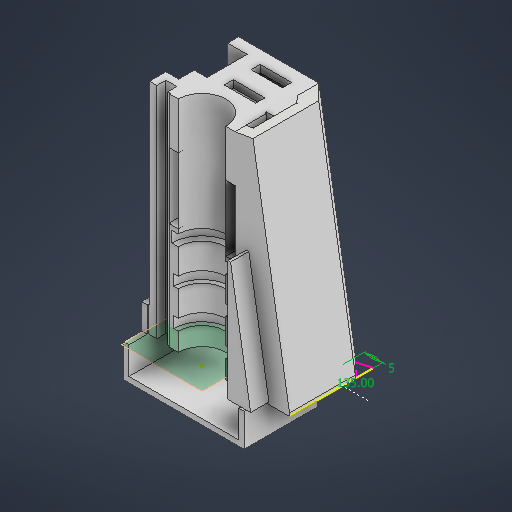
# Autodesk Inventor part: bottom2
Saved by Autodesk Inventor 2026.3 (Build 303398000, 398)
## iProperties
Created: 2026-07-23
Part Number: bottom2
Material: Generic
Document SubType Name: Modeling
Designer: BenFr
Density: 1 g/cm^3
Appearance: Default
Author: BenFr
Autodesk Inventor part; units mm, degrees
ref_plane "YZ Plane" through (0, 0, 0) normal (1, 0, 0) x (0, 1, 0)
ref_plane "XZ Plane" through (0, 0, 0) normal (0, 1, 0) x (-1, 0, 0)
ref_plane "XY Plane" through (0, 0, 0) normal (0, 0, 1) x (1, 0, 0)
sketch "Sketch1" plane through (0, 0, 0) normal (0, 1, 0) x (-1, 0, 0)
  line L0 (-10, 0) -> (0, 0)
  circle A0 centre (0, 0) radius 9
  circle A1 centre (0, 0) radius 6.5
  line L1 (0, 0) -> (9, 0)
  point P0 (6.5, 0)
  point P1 (-9, 0)
  point P2 (-6.5, 0)
  dimension "d1" = 18
  dimension "d0" = 10
  dimension "d2" = 13
  constraints: 4 end point, 2 coincident, 2 horizontal, 1 centre point, 3 other
  measures "d0" distance of L0.start L0.end
  measures "d2" diameter of A1
extrude "Extrusion1" add sketch "Sketch1" along normal blind 60 contours A0 L1 A1 L0 picked at (-3.9988, 7.0571)
sketch "Sketch2" plane through (9, 0, 0) normal (0, 0, -1) x (-1, 0, 0)
  line L0 (0, 60) -> (-10, 0)
  line L1 (-10, 0) -> (0, 0)
  line L2 (0, 0) -> (0, 60)
  line L3 (0, 0) -> (0, 60) projected
  point P0 (9, 0)
  dimension "d5" = 10
  constraints: 6 end point, 2 collinear, 1 horizontal, 1 perpendicular
  measures "d5" distance of L0.end L1.end
extrude "Extrusion2" add sketch "Sketch2" against normal blind 9
sketch "Sketch3" plane through (9, 60, 9) normal (0.9863939, 0.164399, 0) x (0, 0, -1)
  line L0 (9, -60.8276) -> (6, -60.8276)
  line L1 (6, -60.8276) -> (6, 0)
  line L2 (6, 0) -> (9, 0)
  line L3 (9, 0) -> (9, -60.8276)
  line L4 (9, 0) -> (0, 0) projected
  line L5 (9, -60.8276) -> (0, -60.8276) projected
  point P0 (9, -57.704)
  point P1 (7.5, 0)
  point P2 (4.5, -60.8276)
  dimension "d8" = 3
  constraints: 8 end point, 3 point on line, 2 midpoint, 2 parallel, 1 horizontal, 1 perpendicular
  measures "d8" distance of L1.end L2.end
extrude "Extrusion3" add sketch "Sketch3" along normal blind 5
sketch "Sketch4" plane through (19, 0, 3) normal (0, 0, 1) x (0.9863939, 0.164399, 0)
  line L0 (0, 60.8276) -> (5, 60.8276) projected
  line L1 (5, 60.8276) -> (2, 60.8276)
  line L2 (2, 60.8276) -> (2, 0)
  line L3 (2, 0) -> (5, 0)
  line L4 (5, 0) -> (5, 60.8276)
  line L5 (0, 0) -> (5, 0) projected
  point P0 (-18.7415, 3.1236)
  point P1 (2, 60.8276)
  dimension "d11" = 3
  constraints: 8 end point, 2 parallel, 1 collinear, 1 horizontal, 1 perpendicular
  measures "d11" distance of L3.end L2.end
extrude "Extrusion4" add sketch "Sketch4" along normal blind 6
sketch "Sketch5" plane through (9, 0, 9) normal (0, 0, 1) x (1, 0, 0)
  line L0 (0, 60) -> (-18, 60) projected
  line L1 (0, 0) -> (-9, 0)
  line L2 (-9, 0) -> (-9, 60)
  line L3 (-9, 60) -> (0, 60)
  line L4 (0, 60) -> (0, 0)
  line L5 (0, 60) -> (0, 0) projected
  point P0 (-9, 0)
  constraints: 8 end point, 2 parallel, 1 collinear, 1 horizontal, 1 midpoint, 1 perpendicular
extrude "Extrusion5" add sketch "Sketch5" against normal up to surface round surface about axis through (0, 0, 0) along (0, 1, 0) radius 9 far side no
ref_plane "Work Plane2" through (0, 5, 0) normal (0, -1, 0) x (1, 0, 0)
sketch "Sketch6" plane through (0, 5, 0) normal (0, -1, 0) x (1, 0, 0)
  circle A0 centre (0, 0) radius 7.75
  dimension "d17" = 15.5
  constraints: 1 centre point, 1 coincident
  measures "d17" diameter of A0
extrude "Extrusion6" cut sketch "Sketch6" against normal blind 3
sketch "Sketch7" plane through (19, 0, 0) normal (0, 0, -1) x (-1, 0, 0)
  line L0 (10, 60) -> (19, 60) projected
  line L1 (0, 0) -> (10, 60) projected
  line L2 (10, 60) -> (0, 0)
  line L3 (19, 0) -> (0, 0) projected
  line L4 (0.7083, 0.6) -> (6.9, 0.6)
  line L5 (6.9, 0.6) -> (6.9, 37.7503)
  line L6 (6.9, 37.7503) -> (0.7083, 0.6)
  line L7 (0, 0) -> (12.5, 0) projected
  line L8 (19, -12.1644) -> (19, 72.9864) projected
  line L9 (10, 60) -> (10, 0)
  line L10 (0, 0) -> (-4.932, 0.822) projected
  line L11 (0, 0) -> (10, 0)
  line L12 (6.1937, 33.5125) -> (6.1937, 33.5125)
  line L13 (6.1937, 33.5125) -> (6.9, 33.5125)
  point P0 (5, 0)
  dimension "d27" = 3.1
  dimension "d28" = 0.6
  dimension "d29" = 0.6
  constraints: 16 end point, 4 perpendicular, 4 point on line, 2 collinear, 2 parallel, 1 horizontal, 1 midpoint
  measures "d27" distance between parallel lines of L9 L5
  measures "d28" distance from line of point (5, 0) L4
  measures "d29" distance between parallel lines of L1 L6
sketch "Sketch8" plane through (0, 0, 0) normal (0, -1, 0) x (1, 0, 0)
  line L0 (19, 0) -> (19, 3) projected
  line L1 (20.9728, 9) -> (23.932, 9) projected
  line L2 (19, 0) -> (23.932, 0)
  line L3 (23.932, 0) -> (23.932, 9)
  line L4 (23.932, 9) -> (19, 9)
  line L5 (19, 9) -> (19, 0)
  point P0 (0, 0)
  constraints: 8 end point, 2 parallel, 1 horizontal, 1 perpendicular
extrude "Extrusion7" add sketch "Sketch8" along normal up to surface surface through (19, 0, 3) normal (0.164399, -0.9863939, 0)
sketch "Sketch9" plane through (19, 0, 9) normal (0, 0, 1) x (0.9863939, 0.164399, 0)
  line L0 (2, 0) -> (0, 0)
  line L1 (0, 0) -> (0, -4.987)
  line L2 (0, -4.987) -> (2, -4.987)
  line L3 (2, -4.987) -> (2, 0)
  line L4 (0, 0) -> (0, 60.8276) projected
  point P0 (-18.7415, 3.1236)
  constraints: 8 end point, 2 parallel, 1 collinear, 1 horizontal, 1 perpendicular
extrude "Extrusion8" cut sketch "Sketch9" against normal blind 5.5
extrude "Extrusion9" add sketch "Sketch7" along normal blind 5 contours L6 L13 L5 L4
mirror "Mirror1" about plane through (0, 0, 0) normal (0, 0, 1) remove original yes
chamfer "Chamfer1" [suppressed]
sketch "Sketch11" plane through (0, 0, 0) normal (0, -1, 0) x (1, 0, 0)
  line L0 (-6.5, 0) -> (-9, 0) projected
  line L1 (-9.6352, -0.2648) -> (-12.6352, -0.2648)
  line L2 (-12.6352, -0.2648) -> (-12.6352, -2.7648)
  line L3 (-12.6352, -2.7648) -> (-9.6352, -2.7648)
  line L4 (-9.6352, -2.7648) -> (-9.6352, -0.2648)
  line L5 (-14.6352, -0.2648) -> (-9.6352, -0.2648)
  line L6 (-9.6352, -0.2648) -> (-9.6352, -4.7648)
  line L7 (-9.6352, -4.7648) -> (-14.6352, -4.7648)
  line L8 (-14.6352, -4.7648) -> (-14.6352, -0.2648)
  line L9 (-9.6352, -4.7648) -> (-11.0302, -4.7648)
  line L10 (-9.6352, -4.7648) -> (-11.0302, -4.7648)
  line L11 (-11.0302, -4.7648) -> (-7.6352, -4.7648)
  arc A0 (-9, 0) -> (0, -9) centre (0, 0) ccw projected
  line L12 (-9.6352, -0.2648) -> (-7.6352, -0.2648)
  line L13 (-7.6352, -0.2648) -> (-7.6352, -4.7648)
  line L14 (-7.6352, -4.7648) -> (-9.6352, -4.7648)
  line L15 (-9.6352, -4.7648) -> (-9.6352, -0.2648)
  point P0 (-12.6352, -0.2648)
  point P1 (-9.6352, -2.7648)
  point P2 (-7.3341, 0)
  point P3 (-8.9961, -0.2648)
  dimension "d35" = 3
  dimension "d36" = 2.5
  dimension "d37" = 2
  dimension "d38" = 2
  dimension "d124" = 2
  constraints: 30 end point, 7 equal length, 5 horizontal, 3 perpendicular, 2 point on line, 2 other
  measures "d35" distance of L3.end L2.end
  measures "d36" distance of L2.end L1.end
  measures "d37" distance between parallel lines of L8 L2
  measures "d38" distance between parallel lines of L3 L7
  measures "d124" distance of L1.start L12.end
extrude "Extrusion10" add sketch "Sketch11" against normal blind 60 contours L12 A0 L11 L6 L4 | L2 L3 L6 L7 L8 L5 | L12 L13 A0
sketch "Sketch12" plane through (23.932, 0, -9) normal (0, 0, -1) x (-1, 0, 0)
  line L0 (2.9592, 0.3288) -> (12.9592, 60.3288) projected
  line L1 (12.9592, 60.3288) -> (10, 60.822)
  line L2 (0, 0) -> (0, 0.822) projected
  line L3 (10, 60.822) -> (0, 0.822)
  line L4 (0, 0.822) -> (0, 0)
  line L5 (0, 0) -> (2.9044, 0) projected
  line L6 (0, 0) -> (2.9044, 0)
  line L7 (2.9044, 0) -> (12.9592, 60.3288)
  point P0 (23.932, 0)
  constraints: 10 end point, 3 perpendicular, 1 collinear, 1 parallel
extrude "Extrusion11" add sketch "Sketch12" along normal blind 14
sketch "Sketch13" plane through (23.932, 0, -23) normal (0, 0, -1) x (-1, 0, 0)
  line L0 (14.932, 60) -> (10, 60.822) projected
  line L1 (4.932, 0) -> (14.932, 60) projected
  line L2 (10, 60.822) -> (14.932, 60)
  line L3 (14.932, 60) -> (36.9113, 60)
  line L4 (23.932, 60) -> (31.5672, 60) projected
  line L5 (36.9113, 60) -> (36.9113, 0)
  line L6 (0, 0) -> (17.432, 0) projected
  line L7 (36.9113, 0) -> (0, 0)
  line L8 (0, 0) -> (10, 60.822)
  line L9 (31.5672, 60) -> (31.682, 0)
  line L10 (30.432, 0) -> (32.932, 0) projected
  point P0 (23.932, 0)
  point P1 (30.7661, 0)
  point P2 (32.9281, 60)
  constraints: 12 end point, 2 collinear, 2 perpendicular, 1 midpoint
extrude "Extrusion12" add sketch "Sketch13" against normal blind 3
sketch "Sketch14" plane through (0, 0, 0) normal (0, -1, 0) x (1, 0, 0)
  line L0 (23.932, 0) -> (23.932, -23) projected
  line L1 (23.932, -14.5) -> (18.932, -19.5)
  line L2 (22.3885, -19.5) -> (12.61, -19.5) projected
  line L3 (23.932, -14.5) -> (31.003, -14.5) construction
  line L4 (23.932, -8.178) -> (12.61, -19.5)
  line L5 (23.932, -8.178) -> (23.932, -23)
  line L6 (23.932, -19.5) -> (12.61, -19.5)
  point P0 (0, 0)
  point P1 (23.432, -18.5)
  dimension "d51" = 135
  dimension "d52" = 5
  constraints: 10 end point, 1 collinear, 1 equal length, 1 horizontal, 1 parallel, 1 point on line, 1 vertical, 3 other
  measures "d51" angle of L1 L3
  measures "d52" horizontal distance of L1.start L1.end
chamfer "Chamfer4" distance 5 angle 45 2 edges at (16.0002, 30.1644, -20) (18.932, 30.822, -23)
sketch "Sketch21" plane through (0, 25, 0) normal (0, 1, 0) x (1, 0, 0)
  circle A0 centre (0, 0) radius 8.25
  dimension "d79" = 16.5
  constraints: 1 centre point, 1 coincident
  measures "d79" diameter of A0
extrude "Extrusion17" [suppressed]
sketch "Sketch22" plane through (0, 0, 0) normal (0, -1, 0) x (1, 0, 0)
  line L0 (0, 0) -> (15, 0)
  line L1 (15, 0) -> (15, -9)
  line L2 (15, -9) -> (0, -9)
  line L3 (0, -9) -> (0, 0)
  line L4 (0, 0) -> (-15, 0)
  line L5 (-15, 0) -> (-15, -9)
  line L6 (-15, -9) -> (0, -9)
  line L7 (0, -9) -> (0, 0)
  line L8 (0, 0) -> (16.5, 0)
  line L9 (16.5, 0) -> (16.5, -10.5)
  line L10 (16.5, -10.5) -> (0, -10.5)
  line L11 (0, -10.5) -> (0, 0)
  line L12 (0, 0) -> (-16.5, 0)
  line L13 (-16.5, 0) -> (-16.5, -10.5)
  line L14 (-16.5, -10.5) -> (0, -10.5)
  line L15 (0, -10.5) -> (0, 0)
  line L16 (0, -9) -> (19, -9)
  line L17 (0, 0) -> (15, 0)
  line L18 (15, 0) -> (15, -15)
  line L19 (15, -15) -> (0, -15)
  line L20 (0, -15) -> (0, 0)
  line L21 (0, 0) -> (-15, 0)
  line L22 (-15, 0) -> (-15, -15)
  line L23 (-15, -15) -> (0, -15)
  line L24 (0, -15) -> (0, 0)
  line L25 (0, 0) -> (-16.5, 0)
  line L26 (-16.5, 0) -> (-16.5, -16.5462)
  line L27 (-16.5, -16.5462) -> (0, -16.5462)
  line L28 (0, -16.5462) -> (0, 0)
  line L29 (-16.5, -16.5) -> (0, -16.5)
  line L30 (0, -16.5) -> (0, 0)
  line L31 (0, 0) -> (-16.5, 0)
  line L32 (-16.5, 0) -> (-16.5, -16.5)
  line L33 (0, 0) -> (16.5, 0)
  line L34 (16.5, 0) -> (16.5, -16.5)
  line L35 (16.5, -16.5) -> (0, -16.5)
  line L36 (0, -16.5) -> (0, 0)
  point P0 (15, 0)
  point P1 (0, -9)
  point P2 (-15, 0)
  point P3 (0, -10.5)
  point P4 (0, -9)
  point P5 (0, -9)
  point P6 (0, -9)
  dimension "d119" = 30
  dimension "d120" = 1.5
  dimension "d121" = 1.5
  dimension "d135" = 15
  constraints: 74 end point, 16 parallel, 9 horizontal, 9 perpendicular, 3 point on line
  measures "d119" distance between parallel lines of L1 L5
  measures "d120" distance between parallel lines of L9 L1
  measures "d121" distance between parallel lines of L14 L6
  measures "d135" distance of L17.end L18.end
extrude "Extrusion18" add sketch "Sketch22" along normal blind 9 and the other way blind 5 contours L8 L9 L16 L1 | L5 L22 L14 L13 L12 | L16 L9 L10 L18 | L10 L34 L35 L28 L19 L18 | L22 L23 L28 L29 L26 L14
sketch "Sketch23" plane through (0, -9, 0) normal (0, -1, 0) x (1, 0, 0)
  line L0 (15, 0) -> (15, -15) projected
  line L1 (0, 0) -> (15, 0)
  line L2 (15, 0) -> (15, -9)
  line L3 (15, -9) -> (9.75, -9)
  line L4 (0, 0) -> (-0.6472, 0)
  line L5 (9.1028, -9) -> (9.75, -9)
  line L6 (-7.75, 0) -> (-6.5, 0) projected
  line L7 (15, -9) -> (-15, -9)
  line L8 (-15, -9) -> (-15, 0)
  line L9 (-15, 0) -> (15, 0)
  line L10 (15, 0) -> (15, -9)
  constraints: 18 end point, 4 parallel, 3 horizontal, 2 perpendicular, 1 point on line
extrude "Extrusion19" add sketch "Sketch23" against normal blind 1.5
chamfer "Chamfer5" distance 0.5 angle 45 1 edges at (14, 30, -9)
sketch "Sketch25" plane through (0, 60, 0) normal (0, 1, 0) x (1, 0, 0)
  line L0 (19, 3) -> (9, 3) projected
  line L1 (21.0276, 15) -> (10.9728, 15) projected
  line L2 (9, 3) -> (10.9728, 3)
  line L3 (10.9728, 3) -> (10.9728, 15)
  line L4 (10.9728, 15) -> (9, 15)
  line L5 (9, 15) -> (9, 3)
  line L6 (16.5, 9) -> (18.4931, 9) projected
  line L7 (5.9586, 20) -> (9, 17) projected
  line L8 (5.9586, 20) -> (10.9728, 20)
  line L9 (10.9728, 20) -> (10.9728, 9)
  line L10 (-3.4772, 16.9) -> (5.1234, 16.9)
  line L11 (5.1234, 16.9) -> (5.1234, 19.4)
  line L12 (5.1228, 20) -> (-3.4772, 20)
  line L13 (-3.4772, 19.4) -> (-3.4772, 16.9)
  line L14 (5.9586, 20) -> (-12.9794, 20) projected
  line L15 (-3.5104, 12.1) -> (5.0902, 12.1)
  line L16 (5.0902, 12.1) -> (5.0902, 9.6)
  line L17 (5.0902, 9.6) -> (-3.5104, 9.6)
  line L18 (-3.5104, 9.6) -> (-3.5104, 12.1)
  line L19 (-12.9794, 23) -> (9, 23) projected
  line L20 (10.9728, 9) -> (5.1228, 9)
  line L21 (5.1228, 9) -> (5.1228, 20)
  line L22 (5.1228, 20) -> (10.9728, 20)
  line L23 (10.9728, 20) -> (10.9728, 9)
  line L24 (5.1228, 9) -> (-7.6352, 9)
  line L25 (-7.6352, 9) -> (-7.6352, 20)
  line L26 (-7.6352, 20) -> (5.1228, 20)
  line L27 (5.1228, 20) -> (5.1228, 9)
  arc A0 (7.75, 0) -> (-7.6352, 1.3288) centre (0, 0) ccw projected
  circle A1 centre (0, 0) radius 9
  arc A2 (0, 9) -> (-7.6352, 4.7648) centre (0, 0) ccw projected
  line L28 (-7.6352, 9) -> (-7.6352, 4.7648)
  line L29 (-3.4772, 19.4) -> (5.1234, 19.4)
  point P0 (9, 9)
  point P1 (-1.9897, 23)
  point P2 (-7.6352, 4.7648)
  point P3 (0, 9)
  point P4 (8.25, 9)
  point P5 (5.1228, 19.4)
  point P6 (5.1228, 16.9)
  point P7 (9, 9)
  dimension "d97" = 2.5
  dimension "d106" = 8.6
  dimension "d107" = 4.8
  dimension "d108" = 2.5
  dimension "d133" = 0
  dimension "d134" = 0.6
  constraints: 48 end point, 10 parallel, 6 perpendicular, 5 horizontal, 2 midpoint, 2 point on line, 1 centre point, 1 coincident, 1 concentric, 1 vertical
  measures "d97" distance of L13.start L10.start
  measures "d106" distance of L12.start L12.end
  measures "d107" distance between parallel lines of L15 L10
  measures "d108" distance of L17.end L15.start
  measures "d133" distance between parallel lines of L12 L14
  measures "d134" distance between parallel lines of L24 L17
extrude "Extrusion21" add sketch "Sketch25" against normal blind 2 contours L20 L5 L4 L3 | L20 L21 L11 L14 L8 L9 L4 L5 | L24 L25 L14 L12 L21 L29 L13 L10 | A1 L28 L24
sketch "Sketch26" plane through (0, 60, 0) normal (0, 1, 0) x (1, 0, 0)
  circle A0 centre (0, 0) radius 9
  line L0 (0, 0) -> (-7.8168, 0)
  line L1 (-7.8168, 0) -> (-7.8168, 9)
  line L2 (-7.8168, 9) -> (0, 9)
  line L3 (0, 9) -> (0, 0)
  line L4 (-7.8168, 9) -> (-11.1331, 9)
  line L5 (-11.1331, 9) -> (-11.1331, 4.5)
  line L6 (-11.1331, 4.5) -> (-7.8168, 4.5)
  line L7 (-7.8168, 4.5) -> (-7.8168, 9)
  point P0 (-7.8168, 4.4607)
  constraints: 16 end point, 4 parallel, 2 horizontal, 2 perpendicular, 1 centre point, 1 coincident
extrude "Extrusion22" add sketch "Sketch26" against normal blind 60 contours A0 L1 L2 | L1 L6 L5 L4
sketch "Sketch27" plane through (-9, 0, 0) normal (0, 0, 1) x (1, 0, 0)
  line L0 (2.5, 47.5) -> (15.5, 47.5)
  line L1 (15.5, 47.5) -> (15.5, 29)
  line L2 (15.5, 29) -> (2.5, 29)
  line L3 (2.5, 29) -> (2.5, 47.5)
  line L4 (2.5, 47.5) -> (15.5, 29) construction
  line L5 (15.5, 47.5) -> (2.5, 29) construction
  line L6 (15.5, 28) -> (3, 28) projected
  line L7 (-0.1, 29.2472) -> (18.1, 29.2472)
  line L8 (18.1, 29.2472) -> (18.1, 47.2528)
  line L9 (18.1, 47.2528) -> (-0.1, 47.2528)
  line L10 (-0.1, 47.2528) -> (-0.1, 29.2472)
  line L11 (-0.1, 29.2472) -> (18.1, 47.2528) construction
  line L12 (18.1, 29.2472) -> (-0.1, 47.2528) construction
  point P0 (9, 0)
  point P1 (9, 38.25)
  point P2 (2.5, 29.2472)
  point P3 (2.5, 47.2528)
  point P4 (15.5, 47.2528)
  point P5 (15.5, 29.2472)
  point P6 (2.5, 28)
  dimension "d100" = 13
  dimension "d101" = 1
  dimension "d102" = 18.5
  dimension "d103" = 2.6
  constraints: 24 end point, 4 midpoint, 4 parallel, 2 horizontal, 2 perpendicular
  measures "d100" distance of L1.end L2.end
  measures "d101" distance between parallel lines of L6 L2
  measures "d102" distance of L0.end L1.end
  measures "d103" distance between parallel lines of L1 L8
extrude "Extrusion23" cut sketch "Sketch27" against normal up to surface (9 mm away) contours L3 L7 L10 L9 | L9 L8 L7 L1
sketch "Sketch28" plane through (0, 60, 0) normal (0, 1, 0) x (1, 0, 0)
  line L0 (-3.4772, 16.9) -> (5.1234, 16.9)
  line L1 (5.1234, 16.9) -> (5.1234, 19.1)
  line L2 (5.1234, 19.1) -> (-3.4772, 19.1)
  line L3 (-3.4772, 19.1) -> (-3.4772, 16.9)
  line L4 (-3.5104, 12.1) -> (5.0902, 12.1) projected
  point P0 (0, 0)
  dimension "d110" = 2.2
  constraints: 8 end point, 3 parallel, 1 horizontal, 1 perpendicular
  measures "d110" distance of L1.end L0.end
extrude "Extrusion24" cut sketch "Sketch28" against normal blind 25
chamfer "Chamfer6" [suppressed]
chamfer "Chamfer7" distance 0.634 angle 45 1 edges at (15.75, 5, -9)
sketch "Sketch29" plane through (-9, 0, 0) normal (0, 0, 1) x (1, 0, 0)
  line L0 (28, 0) -> (-3.9794, 0) projected
  line L1 (9, -22.9644) -> (9, 74.7864) projected
  point P0 (-6, -7.5)
  point P1 (15.75, 0)
  constraints: 1 point on line
extrude "Extrusion25" [suppressed]
sketch "Sketch30" plane through (-15, 0, -9) normal (0, 0, 1) x (1, 0, 0)
  line L0 (1.5, -5) -> (1.5, -3.5) projected
  line L1 (0, 5) -> (0, -3.5) projected
  line L2 (1.5, -3.5) -> (0, -3.5)
  line L3 (0, -3.5) -> (0, -5)
  line L4 (0, -5) -> (1.5, -5)
  line L5 (1.5, -5) -> (1.5, -3.5)
  point P0 (15, 0)
  point P1 (0, 0)
  point P2 (0, -3.5)
  constraints: 8 end point, 2 parallel, 1 horizontal, 1 perpendicular
extrude "Extrusion26" [suppressed]
sketch "Sketch31" plane through (-9, 0, 0) normal (0, 0, 1) x (1, 0, 0)
  line L0 (-6, -7.5) -> (24, -7.5) projected
  line L1 (-6, 7.5) -> (24, 7.5)
  line L2 (24, 7.5) -> (24, -7.5)
  line L3 (24, -7.5) -> (-6, -7.5)
  line L4 (-6, -7.5) -> (-6, 7.5)
  line L5 (-6, 7.5) -> (24, -7.5) construction
  line L6 (24, 7.5) -> (-6, -7.5) construction
  line L7 (25.5, 0) -> (25.5, -9) projected
  line L8 (-7.5, 9) -> (25.5, 9)
  line L9 (25.5, 9) -> (25.5, -9)
  line L10 (25.5, -9) -> (-7.5, -9)
  line L11 (-7.5, -9) -> (-7.5, 9)
  line L12 (-7.5, 9) -> (25.5, -9) construction
  line L13 (25.5, 9) -> (-7.5, -9) construction
  line L14 (-3.9794, 0) -> (24.9586, 0) projected
  line L15 (-7.5, 0) -> (25.5, 0)
  point P0 (9, 0)
  point P1 (24, 0)
  point P2 (2.25, 0)
  point P3 (-6, 0)
  constraints: 26 end point, 5 midpoint, 4 parallel, 3 horizontal, 2 perpendicular, 1 point on line
extrude "Extrusion27" add sketch "Sketch31" along normal blind 5 and the other way blind 15 contours L0 L2 L14 L15 L7 L10 L11 L4
sketch "Sketch32" plane through (0, 5, 0) normal (0, 1, 0) x (1, 0, 0)
  line L0 (-16.5, 0) -> (16.5, 0)
  line L1 (16.5, 0) -> (16.5, 16.5)
  line L2 (16.5, 16.5) -> (-16.5, 16.5)
  line L3 (-16.5, 16.5) -> (-16.5, 0)
  line L4 (-15, 0) -> (-15, 15) projected
  line L5 (-15, 0) -> (15, 0)
  line L6 (15, 0) -> (15, 9)
  line L7 (15, 9) -> (-15, 9)
  line L8 (-15, 9) -> (-15, 0)
  point P0 (0, 0)
  point P1 (-15, 9)
  point P2 (15, 0)
  constraints: 16 end point, 4 parallel, 2 horizontal, 2 perpendicular
extrude "Extrusion28" add sketch "Sketch32" along normal blind 2 contours L3 L2 L1 L0 L6 L7 L4
sketch "Sketch33" plane through (0, 5, 0) normal (0, -1, 0) x (1, 0, 0)
  circle A0 centre (0, 0) radius 7.75
  constraints: 1 centre point, 1 coincident
extrude "Extrusion29" cut sketch "Sketch33" against normal blind 3
pattern_linear "Rectangular Pattern2" count 3 spacing 10 along (0, 1, 0) of "Extrusion29"
sketch "Sketch34" plane through (0, 25, 0) normal (0, 1, 0) x (1, 0, 0)
  circle A0 centre (0, 0) radius 8.25
  dimension "d145" = 16.5
  constraints: 1 centre point, 1 coincident
  measures "d145" diameter of A0
extrude "Extrusion30" cut sketch "Sketch34" along normal blind 3
chamfer "Chamfer8" distance 3.866 angle 45 1 edges at (-15, 6, -9)
sketch "Sketch35" plane through (-14.6352, 0, -0.2648) normal (0, 0, 1) x (1, 0, 0)
  line L0 (-1.8648, 7) -> (-0.3648, 7) projected
  line L1 (2, 0) -> (2, 60) projected
  line L2 (-1.8648, 7) -> (2, 7)
  line L3 (2, 7) -> (2, 0)
  line L4 (2, 0) -> (-1.8648, 0)
  line L5 (-1.8648, 0) -> (-1.8648, 7)
  point P0 (14.6352, 0)
  constraints: 8 end point, 2 parallel, 1 horizontal, 1 perpendicular
extrude "Extrusion31" add sketch "Sketch35" against normal blind 3
chamfer "Chamfer9" distance 1.5 angle 45 2 edges at (-16.5, -1, -16.5) (16.5, -1, -16.5)
equation "\"d6\" = 0.5 * d1"
body "Solid1"
